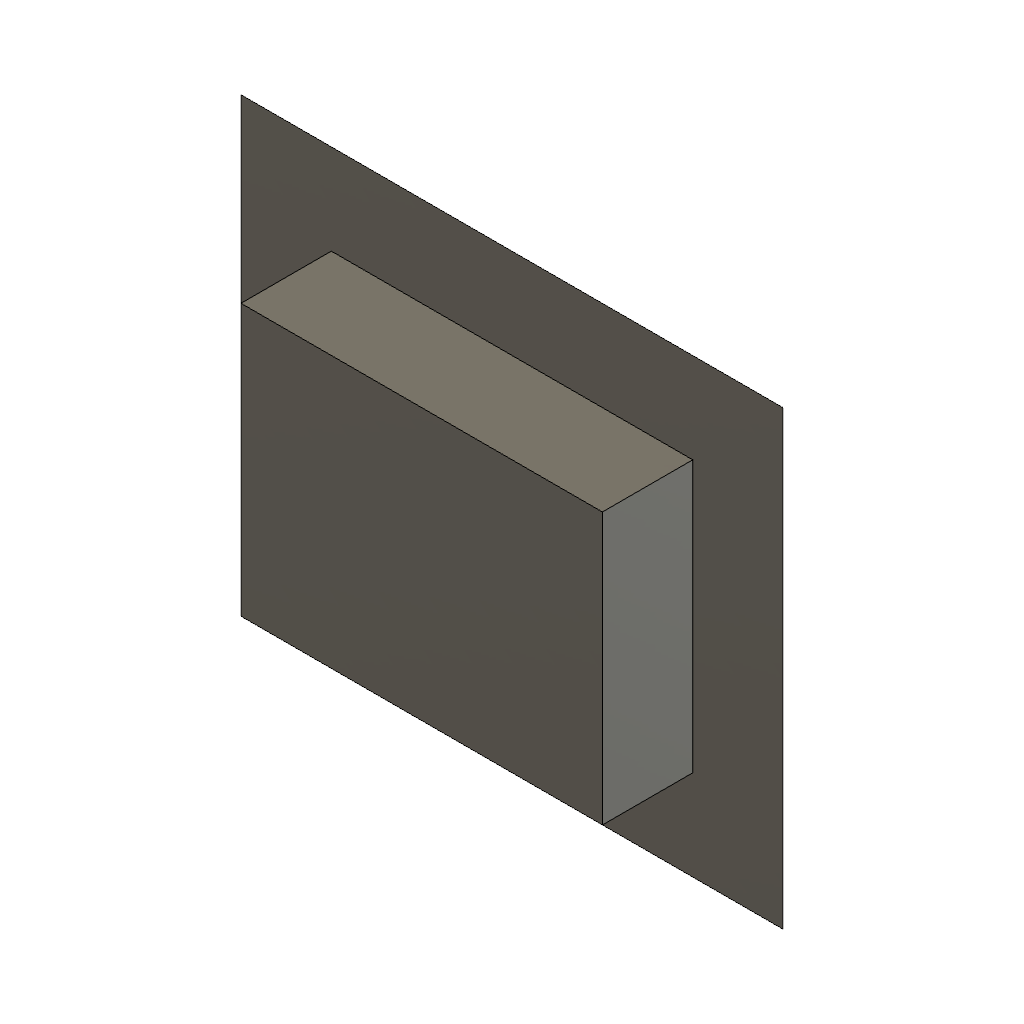
sheet_face_no_extend (Autodesk Fusion 360 design; units mm, degrees)
part number: 2026-10-21-16-14-21-695
Autodesk Fusion 360 part; units mm, degrees
sketch "OwnedSplitBlockProfile_sheet_face_no_extend" plane through (0, 0, 0) normal (0, 0, 1) x (1, 0, 0)
  line L0 (0, 0) -> (40, 0)
  line L1 (40, 0) -> (40, 30)
  line L2 (40, 30) -> (0, 30)
  line L3 (0, 30) -> (0, 0)
extrude "OwnedSplitBlockExtrude_sheet_face_no_extend" add sketch "OwnedSplitBlockProfile_sheet_face_no_extend" along normal blind 20 makes body 1
ref_plane "WorkPlane1" through (0, 0, 10) normal (0, 0, 1) x (1, 0, 0)
sketch "OwnedSplitPatchBoundary_sheet_face_no_extend" plane through (0, 0, 10) normal (0, 0, 1) x (1, 0, 0)
  line L0 (-10, -10) -> (50, -10)
  line L1 (50, -10) -> (50, 40)
  line L2 (50, 40) -> (-10, 40)
  line L3 (-10, 40) -> (-10, -10)
surface "OwnedSplitToolPatch_sheet_face_no_extend" add patch profiles "OwnedSplitPatchBoundary_sheet_face_no_extend" section 1 separate body makes body 2
split "OwnedSplitBodySheet_sheet_face_no_extend" by plane through (0, 0, 10) normal (0, 0, 1) bodies 1 makes body 3 at (13.3333, 20, 20)
named bodies: "OwnedSplitBlock_sheet_face_no_extend", "OwnedSplitToolSheet_sheet_face_no_extend", "OwnedSplitBlock_sheet_face_no_extend (1)"
